CaseCartLid (Autodesk Fusion 360 design; units mm, degrees)
Autodesk Fusion 360 part; units mm, degrees
sketch "Sketch7" plane through (0, 0, 0) normal (1, 0, 0) x (0, 0, -1)
  circle A0 centre (0, 0) radius 4.15
  line L0 (0, 0) -> (-3.594, -2.075)
  line L1 (0, 0) -> (3.594, -2.075)
  line L2 (0, 0) -> (0, 4.15)
  line L3 (-3.594, -2.075) -> (-5.6725, -3.275)
  line L4 (3.594, -2.075) -> (5.6725, -3.275)
  line L5 (0, 4.15) -> (0, 6.55)
  line L6 (-5.6725, -3.275) -> (-10.4356, -6.025)
  line L7 (0, 6.55) -> (0, 12.05)
  line L8 (5.6725, -3.275) -> (10.4356, -6.025)
  circle A1 centre (-10.4356, -6.025) radius 5.5
  circle A2 centre (0, 12.05) radius 5.5
  circle A3 centre (10.4356, -6.025) radius 5.5
  line L9 (-10.4356, -6.025) -> (-10.4356, -11.525)
  line L10 (-10.4356, -11.525) -> (-10.4356, -13.925)
  line L11 (10.4356, -6.025) -> (10.4356, -11.525)
  line L12 (10.4356, -11.525) -> (10.4356, -13.925)
  line L13 (10.4356, -6.025) -> (15.9356, -6.025)
  line L14 (15.9356, -6.025) -> (18.3356, -6.025)
  line L15 (0, 12.05) -> (0, 17.55)
  line L16 (0, 17.55) -> (0, 19.95)
  line L17 (-10.4356, -6.025) -> (-15.9356, -6.025)
  line L18 (-15.9356, -6.025) -> (-18.3356, -6.025)
  line L19 (0, 12.05) -> (5.5, 12.05)
  line L20 (0, 12.05) -> (-5.5, 12.05)
  line L21 (5.5, 12.05) -> (7.9, 12.05)
  line L22 (-5.5, 12.05) -> (-7.9, 12.05)
  line L23 (-10.4356, -6.025) -> (-10.4356, -0.525)
  line L24 (-10.4356, -0.525) -> (-10.4356, 1.875)
  line L25 (10.4356, -6.025) -> (10.4356, -0.525)
  line L26 (-10.4356, -13.925) -> (10.4356, -13.925)
  line L27 (10.4356, -0.525) -> (10.4356, 1.875)
  arc A4 (7.9, 12.05) -> (-7.9, 12.05) centre (0, 12.05) ccw
  arc A5 (-10.4356, 1.875) -> (-10.4356, -13.925) centre (-10.4356, -6.025) ccw
  arc A6 (10.4356, -13.925) -> (10.4356, 1.875) centre (10.4356, -6.025) ccw
  line L28 (0, 12.05) -> (-5.5861, 17.6361)
  line L29 (0, 12.05) -> (7.9, 12.05) construction
  line L30 (0, 12.05) -> (5.5861, 17.6361)
  line L31 (0, 12.05) -> (7.9, 12.05) construction
  line L32 (17.1356, -1.8393) -> (6.8425, 15.9984)
  line L33 (-6.8425, 15.9984) -> (-17.1356, -1.8393)
  line L34 (0, -4.15) -> (0, -13.925)
  line L35 (3.594, 2.075) -> (12.0573, 6.9613)
  line L36 (-3.594, 2.075) -> (-12.0573, 6.9613)
  circle A7 centre (7.8257, 4.5181) radius 1.9
  circle A8 centre (-7.8257, 4.5181) radius 1.9
  circle A9 centre (0, -9.0375) radius 1.9
  dimension "d125" = 2.4
  dimension "d126" = 2.4
  dimension "d127" = 2.4
  dimension "d128" = 5.5
  dimension "d129" = 5.5
  dimension "d130" = 5.5
  dimension "d131" = 11
  dimension "d132" = 11
  dimension "d133" = 11
  dimension "d134" = 2.4
  dimension "d135" = 2.4
  dimension "d136" = 2.4
  dimension "d137" = 2.4
  dimension "d138" = 2.4
  dimension "d139" = 2.4
  dimension "d140" = 2.4
  dimension "d141" = 2.4
  dimension "d142" = 2.4
  dimension "d143" = 135
  dimension "d152" = 3.8
  dimension "d153" = 3.8
  dimension "d154" = 3.8
  constraint coincident A0.centre L0.start
  constraint coincident A0 L2.end
  constraint vertical L2
  constraint parallel L0 L3
  constraint parallel L1 L4
  constraint parallel L2 L5
  constraint parallel L3 L6
  constraint parallel L5 L7
  constraint parallel L4 L8
  constraint coincident L6.end A1.centre
  constraint coincident L7.end A2.centre
  constraint coincident L8.end A3.centre
  constraint coincident A1 L9.end
  constraint vertical L9
  constraint parallel L9 L10
  constraint coincident A3 L11.end
  constraint vertical L11
  constraint parallel L11 L12
  constraint coincident A3 L13.end
  constraint perpendicular L11 L13
  constraint perpendicular L11 L14
  constraint coincident A2 L15.end
  constraint parallel L7 L15
  constraint parallel L15 L16
  constraint coincident A1 L17.end
  constraint perpendicular L9 L17
  constraint parallel L17 L18
  constraint coincident A2 L19.end
  constraint perpendicular L15 L19
  constraint coincident A2 L20.end
  constraint perpendicular L7 L20
  constraint parallel L19 L21
  constraint parallel L20 L22
  constraint coincident A1 L23.end
  constraint perpendicular L17 L23
  constraint parallel L23 L24
  constraint coincident A3 L25.end
  constraint perpendicular L13 L25
  constraint perpendicular L12 L26
  constraint parallel L25 L27
  constraint coincident L16.end A4
  constraint coincident L18.end A5
  constraint coincident L14.end A6
  constraint horizontal L29
  constraint perpendicular L28 L30
  constraint horizontal L31
  constraint coincident A6 L32.start
  constraint coincident A4 L32.end
  constraint tangent A4 L32
  constraint coincident A4 L33.start
  constraint coincident A5 L33.end
  constraint tangent A4 L33
  constraint coincident A0 L34.start
  constraint midpoint L26 L34.end
  constraint perpendicular L26 L34
  constraint coincident L33 L36.end
  constraint coincident L32 L35.end
  constraint coincident A0 L35.start
  constraint coincident A0 L36.start
  constraint midpoint L35 A7.centre
  constraint midpoint L36 A8.centre
  constraint midpoint L34 A9.centre
  measures "d125" distance of L0.end L3.end
  measures "d126" distance of L1.end L4.end
  measures "d127" distance of L2.end L5.end
  measures "d128" distance of L3.end L6.end
  measures "d129" distance of L5.end L7.end
  measures "d130" distance of L4.end L8.end
  measures "d131" diameter of A1
  measures "d132" diameter of A2
  measures "d133" diameter of A3
  measures "d134" distance of L9.end L10.end
  measures "d135" distance of L11.end L12.end
  measures "d136" distance of L13.end L14.end
  measures "d137" distance of L15.end L16.end
  measures "d138" distance of L17.end L18.end
  measures "d139" distance of L19.end L21.end
  measures "d140" distance of L20.end L22.end
  measures "d141" distance of L23.end L24.end
  measures "d142" distance of L25.end L27.end
  measures "d143" angle of L28 L29
  measures "d152" diameter of A7
  measures "d153" diameter of A8
  measures "d154" diameter of A9
extrude "Extrude13" add sketch "Sketch7" along normal blind 14.5
extrude "Extrude14" cut sketch "Sketch7" along normal blind 3 contours A0 L1 L2 | A0 L0 L1 | A0 L0 L2
extrude "Extrude15" cut sketch "Sketch7" along normal blind 12.5 contours L8 A3 L25 | L8 A3 L11 | L7 A2 L20 | L7 A2 L19 | A3 L11 L13 | A3 L13 L25 | A2 L15 L28 | A2 L19 L30 | A2 L20 L28 | A2 L15 L30 | L6 A1 L9 | L6 A1 L23 | A1 L9 L17 | A1 L17 L23
extrude "Extrude16" add sketch "Sketch7" against normal blind 4 contours L35 A7 | L35 A7 | L34 A9 | L34 A9 | L36 A8 | L36 A8
chamfer "Chamfer3" distance 1 angle 45 3 edges at (-4, -8.3504, 1.7714) (-4, 5.2052, 9.5971) (-4, 5.2052, -6.0542) tangent chain off
extrude "Extrude8" [suppressed]
extrude "Extrude9" [suppressed]
extrude "Extrude10" [suppressed]
extrude "Extrude11" [suppressed]
chamfer "Chamfer1" [suppressed]
sketch "Sketch8" plane through (3, 0, 0) normal (-1, 0, 0) x (0, 0, 1)
  circle A0 centre (0, 0) radius 4.15
extrude "Extrude12" [suppressed]
chamfer "Chamfer2" [suppressed]
fillet "Fillet3" [suppressed]
